Autodesk Fusion 360 part; units mm, degrees
(part 3 of 3)
equation "d408 = abs(( frameZ + 20 mm ) * -1)"
equation "d409 = ( panelHeight - 4 mm ) * 1.0"
equation "d411 = ( 2 mm ) * 1.0"
equation "d413 = abs(( ( 10 mm ) + ( -profileMouth / 2 ) ) * 1)"
equation "d414 = abs(( frameZ + ( 0 mm ) ) * -1)"
equation "d415 = abs(( frameZ + ( profileLip ) ) * -1)"
equation "d416 = abs(( ( 10 mm ) + ( -profileCavity / 2 ) ) * 1)"
equation "d417 = abs(( frameZ + ( profileTaperStart ) ) * -1)"
equation "d418 = abs(( ( 10 mm ) + ( -profileFloor / 2 ) ) * 1)"
equation "d419 = abs(( frameZ + ( profileDepth ) ) * -1)"
equation "d420 = abs(( ( 10 mm ) + ( profileFloor / 2 ) ) * 1)"
equation "d421 = abs(( ( 10 mm ) + ( profileCavity / 2 ) ) * 1)"
equation "d422 = abs(( ( 10 mm ) + ( profileMouth / 2 ) ) * 1)"
equation "d423 = ( panelHeight - 4 mm ) * 1.0"
equation "d425 = ( 2 mm ) * 1.0"
equation "d427 = abs(( ( 10 mm ) + 10 mm - ( 0 mm ) ) * 1)"
equation "d428 = abs(( frameZ + 10 mm + ( -profileMouth / 2 ) ) * -1)"
equation "d429 = abs(( ( 10 mm ) + 10 mm - ( profileLip ) ) * 1)"
equation "d430 = abs(( frameZ + 10 mm + ( -profileCavity / 2 ) ) * -1)"
equation "d431 = abs(( ( 10 mm ) + 10 mm - ( profileTaperStart ) ) * 1)"
equation "d432 = abs(( ( 10 mm ) + 10 mm - ( profileDepth ) ) * 1)"
equation "d433 = abs(( frameZ + 10 mm + ( -profileFloor / 2 ) ) * -1)"
equation "d434 = abs(( frameZ + 10 mm + ( profileFloor / 2 ) ) * -1)"
equation "d435 = abs(( frameZ + 10 mm + ( profileCavity / 2 ) ) * -1)"
equation "d436 = abs(( frameZ + 10 mm + ( profileMouth / 2 ) ) * -1)"
equation "d437 = ( panelHeight - 4 mm ) * 1.0"
equation "d439 = ( 2 mm ) * 1.0"
equation "d441 = abs(( ( 10 mm ) - ( -profileMouth / 2 ) ) * 1)"
equation "d442 = abs(( frameZ + 20 mm - ( 0 mm ) ) * -1)"
equation "d443 = abs(( frameZ + 20 mm - ( profileLip ) ) * -1)"
equation "d444 = abs(( ( 10 mm ) - ( -profileCavity / 2 ) ) * 1)"
equation "d445 = abs(( frameZ + 20 mm - ( profileTaperStart ) ) * -1)"
equation "d446 = abs(( ( 10 mm ) - ( -profileFloor / 2 ) ) * 1)"
equation "d447 = abs(( frameZ + 20 mm - ( profileDepth ) ) * -1)"
equation "d448 = abs(( ( 10 mm ) - ( profileFloor / 2 ) ) * 1)"
equation "d449 = abs(( ( 10 mm ) - ( profileCavity / 2 ) ) * 1)"
equation "d450 = abs(( ( 10 mm ) - ( profileMouth / 2 ) ) * 1)"
equation "d451 = ( panelHeight - 4 mm ) * 1.0"
equation "d453 = ( 2 mm ) * 1.0"
equation "d455 = abs(( frameZ + 10 mm - ( -profileMouth / 2 ) ) * -1)"
equation "d456 = abs(( ( 10 mm ) - 10 mm + ( profileLip ) ) * 1)"
equation "d457 = abs(( frameZ + 10 mm - ( -profileCavity / 2 ) ) * -1)"
equation "d458 = abs(( ( 10 mm ) - 10 mm + ( profileTaperStart ) ) * 1)"
equation "d459 = abs(( ( 10 mm ) - 10 mm + ( profileDepth ) ) * 1)"
equation "d460 = abs(( frameZ + 10 mm - ( -profileFloor / 2 ) ) * -1)"
equation "d461 = abs(( frameZ + 10 mm - ( profileFloor / 2 ) ) * -1)"
equation "d462 = abs(( frameZ + 10 mm - ( profileCavity / 2 ) ) * -1)"
equation "d463 = abs(( frameZ + 10 mm - ( profileMouth / 2 ) ) * -1)"
equation "d464 = ( panelHeight - 4 mm ) * 1.0"
equation "d466 = ( 2 mm ) * 1.0"
equation "d468 = abs(( 10 mm ) * 1)"
equation "d469 = abs(( frameZ + 10 mm ) * -1)"
equation "d470 = profileBore"
equation "d471 = ( panelHeight - 4 mm ) * 1.0"
equation "d473 = ( 2 mm ) * 1.0"
equation "d475 = abs(( ( panelWidth ) - 10 mm ) * 1)"
equation "d476 = abs(( frameZ ) * -1)"
equation "d477 = abs(( ( panelWidth ) + 10 mm ) * 1)"
equation "d478 = abs(( frameZ + 20 mm ) * -1)"
equation "d479 = ( panelHeight - 4 mm ) * 1.0"
equation "d481 = ( 2 mm ) * 1.0"
equation "d483 = abs(( ( panelWidth ) + ( -profileMouth / 2 ) ) * 1)"
equation "d484 = abs(( frameZ + ( 0 mm ) ) * -1)"
equation "d485 = abs(( frameZ + ( profileLip ) ) * -1)"
equation "d486 = abs(( ( panelWidth ) + ( -profileCavity / 2 ) ) * 1)"
equation "d487 = abs(( frameZ + ( profileTaperStart ) ) * -1)"
equation "d488 = abs(( ( panelWidth ) + ( -profileFloor / 2 ) ) * 1)"
equation "d489 = abs(( frameZ + ( profileDepth ) ) * -1)"
equation "d490 = abs(( ( panelWidth ) + ( profileFloor / 2 ) ) * 1)"
equation "d491 = abs(( ( panelWidth ) + ( profileCavity / 2 ) ) * 1)"
equation "d492 = abs(( ( panelWidth ) + ( profileMouth / 2 ) ) * 1)"
equation "d493 = ( panelHeight - 4 mm ) * 1.0"
equation "d495 = ( 2 mm ) * 1.0"
equation "d497 = abs(( ( panelWidth ) + 10 mm - ( 0 mm ) ) * 1)"
equation "d498 = abs(( frameZ + 10 mm + ( -profileMouth / 2 ) ) * -1)"
equation "d499 = abs(( ( panelWidth ) + 10 mm - ( profileLip ) ) * 1)"
equation "d500 = abs(( frameZ + 10 mm + ( -profileCavity / 2 ) ) * -1)"
equation "d501 = abs(( ( panelWidth ) + 10 mm - ( profileTaperStart ) ) * 1)"
equation "d502 = abs(( ( panelWidth ) + 10 mm - ( profileDepth ) ) * 1)"
equation "d503 = abs(( frameZ + 10 mm + ( -profileFloor / 2 ) ) * -1)"
equation "d504 = abs(( frameZ + 10 mm + ( profileFloor / 2 ) ) * -1)"
equation "d505 = abs(( frameZ + 10 mm + ( profileCavity / 2 ) ) * -1)"
equation "d506 = abs(( frameZ + 10 mm + ( profileMouth / 2 ) ) * -1)"
equation "d507 = ( panelHeight - 4 mm ) * 1.0"
equation "d509 = ( 2 mm ) * 1.0"
equation "d511 = abs(( ( panelWidth ) - ( -profileMouth / 2 ) ) * 1)"
equation "d512 = abs(( frameZ + 20 mm - ( 0 mm ) ) * -1)"
equation "d513 = abs(( frameZ + 20 mm - ( profileLip ) ) * -1)"
equation "d514 = abs(( ( panelWidth ) - ( -profileCavity / 2 ) ) * 1)"
equation "d515 = abs(( frameZ + 20 mm - ( profileTaperStart ) ) * -1)"
equation "d516 = abs(( ( panelWidth ) - ( -profileFloor / 2 ) ) * 1)"
equation "d517 = abs(( frameZ + 20 mm - ( profileDepth ) ) * -1)"
equation "d518 = abs(( ( panelWidth ) - ( profileFloor / 2 ) ) * 1)"
equation "d519 = abs(( ( panelWidth ) - ( profileCavity / 2 ) ) * 1)"
equation "d520 = abs(( ( panelWidth ) - ( profileMouth / 2 ) ) * 1)"
equation "d521 = ( panelHeight - 4 mm ) * 1.0"
equation "d523 = ( 2 mm ) * 1.0"
equation "d525 = abs(( ( panelWidth ) - 10 mm + ( 0 mm ) ) * 1)"
equation "d526 = abs(( frameZ + 10 mm - ( -profileMouth / 2 ) ) * -1)"
equation "d527 = abs(( ( panelWidth ) - 10 mm + ( profileLip ) ) * 1)"
equation "d528 = abs(( frameZ + 10 mm - ( -profileCavity / 2 ) ) * -1)"
equation "d529 = abs(( ( panelWidth ) - 10 mm + ( profileTaperStart ) ) * 1)"
equation "d530 = abs(( ( panelWidth ) - 10 mm + ( profileDepth ) ) * 1)"
equation "d531 = abs(( frameZ + 10 mm - ( -profileFloor / 2 ) ) * -1)"
equation "d532 = abs(( frameZ + 10 mm - ( profileFloor / 2 ) ) * -1)"
equation "d533 = abs(( frameZ + 10 mm - ( profileCavity / 2 ) ) * -1)"
equation "d534 = abs(( frameZ + 10 mm - ( profileMouth / 2 ) ) * -1)"
equation "d535 = ( panelHeight - 4 mm ) * 1.0"
equation "d537 = ( 2 mm ) * 1.0"
equation "d539 = abs(( panelWidth ) * 1)"
equation "d540 = abs(( frameZ + 10 mm ) * -1)"
equation "d541 = profileBore"
equation "d542 = ( panelHeight - 4 mm ) * 1.0"
equation "d544 = ( 2 mm ) * 1.0"
equation "d546 = abs(( ( 2 * panelWidth - 10 mm ) - 10 mm ) * 1)"
equation "d547 = abs(( frameZ ) * -1)"
equation "d548 = abs(( ( 2 * panelWidth - 10 mm ) + 10 mm ) * 1)"
equation "d549 = abs(( frameZ + 20 mm ) * -1)"
equation "d550 = ( panelHeight - 4 mm ) * 1.0"
equation "d552 = ( 2 mm ) * 1.0"
equation "d554 = abs(( ( 2 * panelWidth - 10 mm ) + ( -profileMouth / 2 ) ) * 1)"
equation "d555 = abs(( frameZ + ( 0 mm ) ) * -1)"
equation "d556 = abs(( frameZ + ( profileLip ) ) * -1)"
equation "d557 = abs(( ( 2 * panelWidth - 10 mm ) + ( -profileCavity / 2 ) ) * 1)"
equation "d558 = abs(( frameZ + ( profileTaperStart ) ) * -1)"
equation "d559 = abs(( ( 2 * panelWidth - 10 mm ) + ( -profileFloor / 2 ) ) * 1)"
equation "d560 = abs(( frameZ + ( profileDepth ) ) * -1)"
equation "d561 = abs(( ( 2 * panelWidth - 10 mm ) + ( profileFloor / 2 ) ) * 1)"
equation "d562 = abs(( ( 2 * panelWidth - 10 mm ) + ( profileCavity / 2 ) ) * 1)"
equation "d563 = abs(( ( 2 * panelWidth - 10 mm ) + ( profileMouth / 2 ) ) * 1)"
equation "d564 = ( panelHeight - 4 mm ) * 1.0"
equation "d566 = ( 2 mm ) * 1.0"
equation "d568 = abs(( ( 2 * panelWidth - 10 mm ) + 10 mm - ( 0 mm ) ) * 1)"
equation "d569 = abs(( frameZ + 10 mm + ( -profileMouth / 2 ) ) * -1)"
equation "d570 = abs(( ( 2 * panelWidth - 10 mm ) + 10 mm - ( profileLip ) ) * 1)"
equation "d571 = abs(( frameZ + 10 mm + ( -profileCavity / 2 ) ) * -1)"
equation "d572 = abs(( ( 2 * panelWidth - 10 mm ) + 10 mm - ( profileTaperStart ) ) * 1)"
equation "d573 = abs(( ( 2 * panelWidth - 10 mm ) + 10 mm - ( profileDepth ) ) * 1)"
equation "d574 = abs(( frameZ + 10 mm + ( -profileFloor / 2 ) ) * -1)"
equation "d575 = abs(( frameZ + 10 mm + ( profileFloor / 2 ) ) * -1)"
equation "d576 = abs(( frameZ + 10 mm + ( profileCavity / 2 ) ) * -1)"
equation "d577 = abs(( frameZ + 10 mm + ( profileMouth / 2 ) ) * -1)"
equation "d578 = ( panelHeight - 4 mm ) * 1.0"
equation "d580 = ( 2 mm ) * 1.0"
equation "d582 = abs(( ( 2 * panelWidth - 10 mm ) - ( -profileMouth / 2 ) ) * 1)"
equation "d583 = abs(( frameZ + 20 mm - ( 0 mm ) ) * -1)"
equation "d584 = abs(( frameZ + 20 mm - ( profileLip ) ) * -1)"
equation "d585 = abs(( ( 2 * panelWidth - 10 mm ) - ( -profileCavity / 2 ) ) * 1)"
equation "d586 = abs(( frameZ + 20 mm - ( profileTaperStart ) ) * -1)"
equation "d587 = abs(( ( 2 * panelWidth - 10 mm ) - ( -profileFloor / 2 ) ) * 1)"
equation "d588 = abs(( frameZ + 20 mm - ( profileDepth ) ) * -1)"
equation "d589 = abs(( ( 2 * panelWidth - 10 mm ) - ( profileFloor / 2 ) ) * 1)"
equation "d590 = abs(( ( 2 * panelWidth - 10 mm ) - ( profileCavity / 2 ) ) * 1)"
equation "d591 = abs(( ( 2 * panelWidth - 10 mm ) - ( profileMouth / 2 ) ) * 1)"
equation "d592 = ( panelHeight - 4 mm ) * 1.0"
equation "d594 = ( 2 mm ) * 1.0"
equation "d596 = abs(( ( 2 * panelWidth - 10 mm ) - 10 mm + ( 0 mm ) ) * 1)"
equation "d597 = abs(( frameZ + 10 mm - ( -profileMouth / 2 ) ) * -1)"
equation "d598 = abs(( ( 2 * panelWidth - 10 mm ) - 10 mm + ( profileLip ) ) * 1)"
equation "d599 = abs(( frameZ + 10 mm - ( -profileCavity / 2 ) ) * -1)"
equation "d600 = abs(( ( 2 * panelWidth - 10 mm ) - 10 mm + ( profileTaperStart ) ) * 1)"
equation "d601 = abs(( ( 2 * panelWidth - 10 mm ) - 10 mm + ( profileDepth ) ) * 1)"
equation "d602 = abs(( frameZ + 10 mm - ( -profileFloor / 2 ) ) * -1)"
equation "d603 = abs(( frameZ + 10 mm - ( profileFloor / 2 ) ) * -1)"
equation "d604 = abs(( frameZ + 10 mm - ( profileCavity / 2 ) ) * -1)"
equation "d605 = abs(( frameZ + 10 mm - ( profileMouth / 2 ) ) * -1)"
equation "d606 = ( panelHeight - 4 mm ) * 1.0"
equation "d608 = ( 2 mm ) * 1.0"
equation "d610 = abs(( 2 * panelWidth - 10 mm ) * 1)"
equation "d611 = abs(( frameZ + 10 mm ) * -1)"
equation "d612 = profileBore"
equation "d613 = ( panelHeight - 4 mm ) * 1.0"
